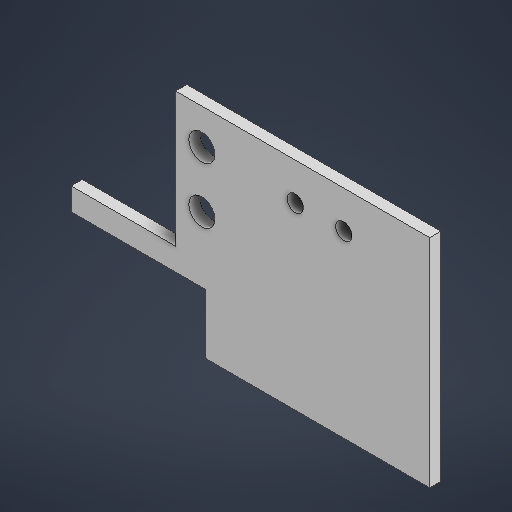
# Autodesk Inventor part: 6_09_plaque_supp_detection3
Saved by Autodesk Inventor 2026 (Build 300175000, 175)
## iProperties
Created: 2025-06-19
Part Number: 6_09_plaque_supp_detection3
Material: Générique
Document SubType Name: Modeling
Designer: Diogo
Density: 1 g/cm^3
Appearance: Par défaut
Author: Diogo
Autodesk Inventor part; units mm, degrees
ref_plane "YZ Plane" through (0, 0, 0) normal (1, 0, 0) x (0, 1, 0)
ref_plane "XZ Plane" through (0, 0, 0) normal (0, 1, 0) x (-1, 0, 0)
ref_plane "XY Plane" through (0, 0, 0) normal (0, 0, 1) x (1, 0, 0)
sketch "Esquisse1" plane through (0, 0, 0) normal (0, 0, 1) x (1, 0, 0)
  line L0 (0, 0) -> (18, 0)
  line L1 (18, 0) -> (18, -8)
  line L2 (0, 0) -> (0, 3)
  line L3 (14, 21) -> (48, 21)
  line L4 (48, 21) -> (48, -8)
  line L5 (48, -8) -> (18, -8)
  line L6 (14, 21) -> (14, 3)
  line L7 (14, 3) -> (0, 3)
  dimension "d0" = 18
  dimension "d1" = 8
  dimension "d2" = 3
  dimension "d5" = 34
  dimension "d6" = 29
  dimension "d53" = 18
  constraints: 16 end point, 3 perpendicular, 2 horizontal, 2 vertical
  measures "d0" distance of L0.start L0.end
  measures "d1" distance of L0.end L1.end
  measures "d2" distance of L0.start L2.end
  measures "d5" distance of L3.start L3.end
  measures "d6" distance of L3.end L4.end
  measures "d53" distance of L3.start L6.end
extrude "Extrusion1" add sketch "Esquisse1" along normal blind 1.5
sketch "Esquisse3" plane through (0, 0, 1.5) normal (0, 0, 1) x (1, 0, 0)
  line L0 (14, 21) -> (21, 21) construction
  line L1 (21, 21) -> (21, 2.2464) construction
  line L2 (21, 2.2464) -> (14, 2.2464) construction
  line L3 (14, 2.2464) -> (14, 21) construction
  circle A0 centre (17.5, 16.25) radius 1.75
  circle A1 centre (17.5, 8.75) radius 1.75
  circle A2 centre (30, 16) radius 1.1
  line L4 (48, 21) -> (14, 21) projected
  circle A3 centre (36.5, 16) radius 1.1
  point P0 (0, 0)
  dimension "d25" = 7
  dimension "d26" = 3.5
  dimension "d27" = 4.75
  dimension "d28" = 3.5
  dimension "d29" = 7.5
  dimension "d48" = 2.2
  dimension "d49" = 9
  dimension "d50" = 5
  dimension "d51" = 2.2
  dimension "d52" = 6.5
  constraints: 8 end point, 4 centre point, 2 parallel, 1 coincident, 1 horizontal, 1 perpendicular
  measures "d25" distance of L2.start L2.end
  measures "d26" diameter of A0
  measures "d27" distance from line of L0 A0.centre
  measures "d28" diameter of A1
  measures "d29" distance of A0.centre A1.centre
  measures "d48" diameter of A2
  measures "d49" horizontal distance of L1.start A2.centre
  measures "d50" distance from line of L4 A2.centre
  measures "d51" diameter of A3
  measures "d52" distance of A2.centre A3.centre
extrude "Extrusion3" cut sketch "Esquisse3" against normal through all
